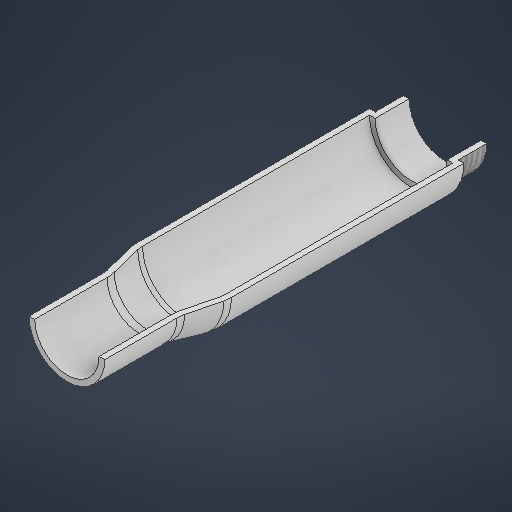
# Autodesk Inventor part: Blender_Upper Housing
Saved by Autodesk Inventor 2027.1 (Build 311270010, 270A)
## iProperties
Created: 2026-10-20
Part Number: Blender_Upper Housing
Material: Generic
Document SubType Name: Modeling
Designer: MSIPC
Density: 1 g/cm^3
Appearance: Default
Author: MSIPC
Autodesk Inventor part; units mm, degrees
ref_plane "YZ Plane" through (0, 0, 0) normal (1, 0, 0) x (0, 1, 0)
ref_plane "XY Plane" through (0, 0, 0) normal (0, 0, 1) x (1, 0, 0)
sketch "Sketch1" plane through (0, 0, 0) normal (0, 1, 0) x (-1, 0, 0)
  line L0 (-25, 15) -> (-25, 138)
  line L1 (-24.5589, 141.611) -> (-20.4411, 158.2132)
  line L2 (-20, 161.8242) -> (-20, 199.9917)
  line L3 (-20, 199.9917) -> (-17, 199.9917)
  line L4 (0, 200) -> (0, 0)
  arc A0 (-20.4411, 158.2132) -> (-20, 161.8242) centre (-35, 161.8242) ccw
  arc A1 (-24.5589, 141.611) -> (-25, 138) centre (-10, 138) ccw
  line L5 (-22, 138) -> (-22, 18)
  line L6 (-17, 199.9917) -> (-17, 161.8242)
  arc A2 (-17.5293, 157.491) -> (-17, 161.8242) centre (-35, 161.8242) ccw
  line L7 (-17.5293, 157.491) -> (-21.6471, 140.8888)
  arc A3 (-21.6471, 140.8888) -> (-22, 138) centre (-10, 138) ccw
  line L8 (-19, 18) -> (-19, 0)
  line L9 (-22, 18) -> (-19, 18)
  line L10 (-25, 15) -> (-22, 15)
  line L11 (-22, 15) -> (-22, 0)
  line L12 (-22, 0) -> (-19, 0)
  point P0 (-25, 139.8324)
  point P1 (-20, 159.9917)
  dimension "d2" = 20
  dimension "d3" = 200
  dimension "d4" = 40
  dimension "d5" = 15
  dimension "d6" = 15
  dimension "d7" = 3
  dimension "d9" = 3
  dimension "d10" = 3
  dimension "d13" = 3
  dimension "d14" = 3
  dimension "d15" = 15
  dimension "d17" = 22
  dimension "d18" = 120
  dimension "d19" = 25
  constraints: 26 end point, 8 point on circle, 4 centre point, 4 point on line, 4 tangent, 3 perpendicular, 2 horizontal, 2 parallel, 1 vertical, 2 other
  measures "d2" distance of L2.end L4.start
  measures "d3" distance of L4.start L4.end
  measures "d4" distance of point (-20, 159.992) L2.end
  measures "d5" radius of A0
  measures "d6" radius of A1
  measures "d7" distance between parallel lines of L0 L5
  measures "d9" distance between parallel lines of L2 L6
  measures "d10" distance between parallel lines of L7 L1
  measures "d13" distance between parallel lines of L9 L10
  measures "d14" distance between parallel lines of L8 L11
  measures "d15" distance from line of L4.end L10
  measures "d17" distance between parallel lines of L4 L11
  measures "d18" distance of L5.start L5.end
  measures "d19" distance between parallel lines of L4 L0
revolve "Revolution1" add sketch "Sketch1" angle 360 about axis through (0, 0, 200) along (0, 0, -1)
thread "Thread1" size "M45x3" class "6g" standard "ANSI Metric M Profile" full length
ref_plane "Work Plane1" through (0, -25, 76.5) normal (0, 1, 0) x (-1, 0, 0)
sketch "Sketch4" plane through (0, -25, 76.5) normal (0, 1, 0) x (-1, 0, 0)
  circle A0 centre (0, 35.7219) radius 10
  point P0 (0, -76.5)
  dimension "d22" = 20
  constraints: 1 centre point
  measures "d22" diameter of A0
extrude "Extrusion1" add sketch "Sketch4" along normal up to surface round surface about axis through (0, 0, 78) along (0, 0, -1) radius 22 far side no
fillet "Fillet1" radius 2 3 edges at (-7.6112, -23.8132, 105.7358) (-7.6096, -23.8137, 118.7099) (10, -22.9129, 112.214)
sketch "Sketch5" plane through (0, 0, 199.9917) normal (0, 0, 1) x (1, 0, 0)
  line L0 (32.2711, 0) -> (-33.1433, 0)
  line L1 (-33.1433, 0) -> (-33.1433, 30.3813)
  line L2 (-33.1433, 30.3813) -> (32.2711, 30.3813)
  line L3 (32.2711, 30.3813) -> (32.2711, 0)
  point P0 (0, 0)
  constraints: 8 end point, 2 parallel, 1 horizontal, 1 perpendicular
extrude "Extrusion2" cut sketch "Sketch5" against normal blind 219
body "Solid1"
